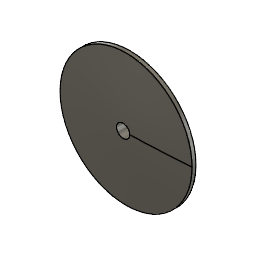
Tapered_Edge (Autodesk Fusion 360 design; units mm, degrees)
part number: 2026-09-02-17-01-32-244
Autodesk Fusion 360 part; units mm, degrees
sketch "Sketch1" plane through (0, 0, 0) normal (0, 1, 0) x (1, 0, 0)
sketch "tapered_disc_profile" plane through (0, 0, 0) normal (0, 1, 0) x (1, 0, 0)
  spline S0 degree 3 poles (10, 7.431) (11.6667, 7.4049) (15.0004, 7.3527) (20.0004, 7.2327) (25.0005, 7.0842) (30.0005, 6.9062) (35.0005, 6.7017) (40.0005, 6.4732) (45.0005, 6.2236) (50.0004, 5.9561) (55.0003, 5.6738) (60.0002, 5.3799) (65.0002, 5.0777) (70.0001, 4.7703) (75, 4.4609) (79.9999, 4.1523) (84.9998, 3.8472) (89.9998, 3.5483) (94.9997, 3.2566) (98.3333, 3.071) (100, 2.9782) knots 0 0 0 0 0.500073 1.000211 1.500432 2.000747 2.501164 3.001683 3.502303 4.003016 4.503809 5.004669 5.505578 6.006519 6.507472 7.008421 7.509348 8.01024 8.511084 9.011871 9.011871 9.011871 9.011871
  line L0 (100, 2.9782) -> (100, -2.9782)
  spline S1 degree 3 poles (100, -2.9782) (98.3333, -3.071) (94.9997, -3.2566) (89.9998, -3.5483) (84.9998, -3.8472) (79.9999, -4.1523) (75, -4.4609) (70.0001, -4.7703) (65.0002, -5.0777) (60.0002, -5.3799) (55.0003, -5.6738) (50.0004, -5.9561) (45.0005, -6.2236) (40.0005, -6.4732) (35.0005, -6.7017) (30.0005, -6.9062) (25.0005, -7.0842) (20.0004, -7.2327) (15.0004, -7.3527) (11.6667, -7.4049) (10, -7.431) knots 0 0 0 0 0.500787 1.001631 1.502523 2.00345 2.504399 3.005352 3.506293 4.007202 4.508062 5.008856 5.509568 6.010188 6.510707 7.011124 7.511439 8.01166 8.511798 9.011871 9.011871 9.011871 9.011871
  line L1 (10, -7.431) -> (10, 7.431)
revolve "Revolve1" add sketch "tapered_disc_profile" angle 360 about axis through (0, 0, 1.75) along (0, 0, 1)
